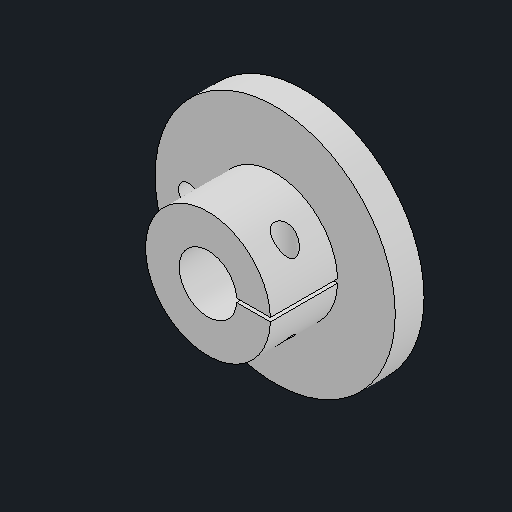
# Autodesk Inventor part: lead-screw-handwheel
Saved by Autodesk Inventor 2027.1 (Build 311270010, 270A)
## iProperties
Created: 2026-11-06
Part Number: lead-screw-handwheel
Material: Generic
Description: Concept: 50 mm handwheel with split clamp hub for 12 mm journal; M4 pinch bolt required
Document SubType Name: Modeling
Designer: queezz
Density: 1 g/cm^3
Appearance: Default
Mass: 16.6688 g
Surface Area: 68.6832 cm^2
Volume: 16.6688 cm^3
Author: queezz
Autodesk Inventor part; units mm, degrees
ref_plane "Wheel rim plane" through (0, 0, 0) normal (0, 0, 1) x (1, 0, 0)
sketch "Wheel rim" plane through (0, 0, 0) normal (0, 0, 1) x (1, 0, 0)
  circle A0 centre (0, 0) radius 25
  dimension "d0" = 50
  constraints: 1 centre point, 1 other
  measures "d0" diameter of A0
extrude "Wheel disc" add sketch "Wheel rim" along normal blind 6
ref_plane "Clamp hub plane" through (0, 0, 0) normal (0, 0, 1) x (1, 0, 0)
sketch "Clamp hub" plane through (0, 0, 0) normal (0, 0, 1) x (1, 0, 0)
  circle A0 centre (0, 0) radius 13
  dimension "d3" = 26
  constraints: 1 centre point, 1 other
  measures "d3" diameter of A0
extrude "Hub" add sketch "Clamp hub" along normal blind 20
ref_plane "Journal bore plane" through (0, 0, 0) normal (0, 0, 1) x (1, 0, 0)
sketch "Journal bore" plane through (0, 0, 0) normal (0, 0, 1) x (1, 0, 0)
  circle A0 centre (0, 0) radius 6
  dimension "d6" = 12
  constraints: 1 centre point, 1 other
  measures "d6" diameter of A0
extrude "Through journal bore" cut sketch "Journal bore" along normal blind 20
ref_plane "Hub split plane" through (0, 0, 6) normal (0, 0, 1) x (1, 0, 0)
sketch "Hub split" plane through (0, 0, 6) normal (0, 0, 1) x (1, 0, 0)
  line L0 (0, -0.4) -> (14, -0.4)
  line L1 (14, -0.4) -> (14, 0.4)
  line L2 (14, 0.4) -> (0, 0.4)
  line L3 (0, 0.4) -> (0, -0.4)
  dimension "d9" = 14
  dimension "d10" = 0.8
  constraints: 8 end point, 2 parallel, 1 horizontal, 1 perpendicular, 1 other
  measures "d9" distance of L0.start L0.end
  measures "d10" distance of L0.end L1.end
extrude "Clamp flexure slot" cut sketch "Hub split" along normal blind 14
ref_plane "Pinch bolt clearance plane" through (0, 14, 0) normal (0, -1, 0) x (1, 0, 0)
sketch "Pinch bolt clearance" plane through (0, 14, 0) normal (0, -1, 0) x (1, 0, 0)
  circle A0 centre (9, 13) radius 2.15
  dimension "d13" = 4.3
  constraints: 1 centre point, 1 other
  measures "d13" diameter of A0
extrude "M4 clearance half" cut sketch "Pinch bolt clearance" along normal blind 13.6
ref_plane "Pinch bolt tap pilot plane" through (0, -0.4, 0) normal (0, -1, 0) x (1, 0, 0)
sketch "Pinch bolt tap pilot" plane through (0, -0.4, 0) normal (0, -1, 0) x (1, 0, 0)
  circle A0 centre (9, 13) radius 1.65
  dimension "d16" = 3.3
  constraints: 1 centre point, 1 other
  measures "d16" diameter of A0
extrude "M4 tap pilot half" cut sketch "Pinch bolt tap pilot" along normal blind 13.6
sketch "Crank grip fastener" plane through (0, 0, 0) normal (0, 0, 1) x (1, 0, 0)
  circle A0 centre (-18, 0) radius 2.15
  dimension "grip_fastener_diameter" = 4.3
  constraints: 1 centre point, 1 other
  measures "grip_fastener_diameter" diameter of A0
extrude "M4 grip through hole" cut sketch "Crank grip fastener" along normal blind 6
equation "\"d0\" = wheel_diameter"
equation "\"d1\" = wheel_thickness"
equation "\"d3\" = hub_diameter"
equation "\"d4\" = hub_length"
equation "\"d6\" = shaft_bore"
equation "\"d7\" = hub_length"
equation "\"d10\" = clamp_slot"
equation "\"d11\" = hub_length - wheel_thickness"
equation "\"d13\" = clamp_clearance"
equation "\"d16\" = clamp_tap_drill"
equation "\"d20\" = wheel_thickness"
equation "\"wheel_diameter\" = 50"
equation "\"wheel_thickness\" = 6"
equation "\"hub_diameter\" = 26"
equation "\"hub_length\" = 20"
equation "\"shaft_bore\" = 12"
equation "\"clamp_slot\" = 0.8"
equation "\"clamp_clearance\" = 4.3"
equation "\"clamp_tap_drill\" = 3.3"
body "Solid1"
